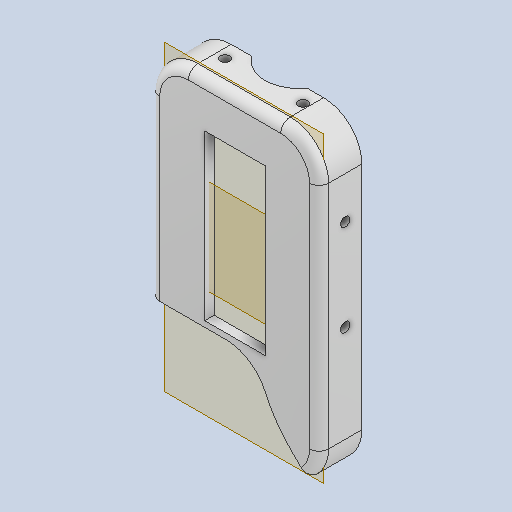
# Autodesk Inventor part: Pieza13
Saved by Autodesk Inventor 2025.2 (Build 292293000, 293)
## iProperties
Created: 2022-03-08
Part Number: Pieza13
Material: Aluminio
Document SubType Name: Modeling
Designer: Fabia
Density: 2.7 g/cm^3
Appearance: Satinado
Author: Fabia
Autodesk Inventor part; units mm, degrees
ref_plane "YZ Plane" through (0, 0, 0) normal (1, 0, 0) x (0, 1, 0)
ref_plane "XZ Plane" through (0, 0, 0) normal (0, 1, 0) x (-1, 0, 0)
ref_plane "Plano de trabajo1" through (0, 0, 1) normal (0, 0, 1) x (1, 0, 0)
sketch "Boceto1" plane through (0, 0, 1) normal (0, 0, 1) x (1, 0, 0)
  line L0 (-15.7261, -14.616) -> (-15.7261, 21.3302)
  arc A0 (-9.7062, 27.3501) -> (-15.7261, 21.3302) centre (-9.7062, 21.3302) ccw
  line L1 (-9.7062, 27.3501) -> (9.7062, 27.3501)
  arc A1 (15.7261, 21.3302) -> (9.7062, 27.3501) centre (9.7062, 21.3302) ccw
  line L2 (15.7261, 21.3302) -> (15.7261, -27.0568)
  arc A2 (13.9629, -31.3135) -> (15.7261, -27.0568) centre (9.7062, -27.0568) ccw
  line L3 (-17.7587, -14.616) -> (-17.7587, 21.3302)
  arc A3 (-9.7062, 29.3827) -> (-17.7587, 21.3302) centre (-9.7062, 21.3302) ccw
  line L4 (-9.7062, 29.3827) -> (9.7062, 29.3827)
  arc A4 (17.7587, 21.3302) -> (9.7062, 29.3827) centre (9.7062, 21.3302) ccw
  line L5 (17.7587, 21.3302) -> (17.7587, -27.0568)
  arc A5 (15.4002, -32.7508) -> (17.7587, -27.0568) centre (9.7062, -27.0568) ccw
  line L6 (15.4002, -32.7508) -> (13.9629, -31.3135)
  line L7 (15.4002, -32.7508) -> (7.7523, -32.7508)
  line L8 (7.7523, -32.7508) -> (7.7523, -15.933)
  line L9 (7.7523, -15.933) -> (-17.7587, -15.933)
  line L10 (-17.7587, -15.933) -> (-17.7587, -14.616)
  line L11 (-15.7261, -14.616) -> (-15.7261, -15.933)
  point P0 (0, 0)
  constraints: 24 end point, 12 point on circle, 6 centre point, 4 perpendicular, 1 horizontal, 1 point on line, 5 other
extrude "Extrusión1" add sketch "Boceto1" against normal blind 8 contours L11 L9 L10 L3 A3 L4 A4 L5 A5 L6 A2 L2 A1 L1 A0 L0
ref_plane "Plano de trabajo2" through (0, 0, 0) normal (0, 0, 1) x (1, 0, 0)
sketch "Boceto2" plane through (0, 0, 0) normal (0, 0, 1) x (1, 0, 0)
  arc A0 (-9.7062, 27.3501) -> (-15.7261, 21.3302) centre (-9.7062, 21.3302) ccw projected
  line L0 (-9.7062, 27.3501) -> (9.7062, 27.3501) projected
  arc A1 (15.7261, 21.3302) -> (9.7062, 27.3501) centre (9.7062, 21.3302) ccw projected
  line L1 (15.7261, 21.3302) -> (15.7261, -27.0568) projected
  arc A2 (13.9629, -31.3135) -> (15.7261, -27.0568) centre (9.7062, -27.0568) ccw projected
  line L2 (13.9629, -31.3135) -> (15.4002, -32.7508) projected
  arc A3 (15.4002, -32.7508) -> (17.7587, -27.0568) centre (9.7062, -27.0568) ccw projected
  line L3 (17.7587, -27.0568) -> (17.7587, 21.3302) projected
  arc A4 (17.7587, 21.3302) -> (9.7062, 29.3827) centre (9.7062, 21.3302) ccw projected
  line L4 (9.7062, 29.3827) -> (-9.7062, 29.3827) projected
  arc A5 (-9.7062, 29.3827) -> (-17.7587, 21.3302) centre (-9.7062, 21.3302) ccw projected
  line L5 (-17.7587, 21.3302) -> (-17.7587, -15.933) projected
  line L6 (-17.7587, -15.933) -> (-15.7261, -15.933) projected
  line L7 (-15.7261, -15.933) -> (-15.7261, 21.3302) projected
  line L8 (-18.3012, -15.933) -> (7.1636, -15.933)
  line L9 (7.1636, -15.933) -> (7.1636, -24.5142)
  line L10 (13.9629, -31.3135) -> (15.4002, -32.7508) projected
  line L11 (7.1636, -24.5142) -> (15.4002, -32.7508)
  line L12 (6.5068, 19.8394) -> (-6.2947, 19.8394)
  line L13 (-6.2947, 19.8394) -> (-6.2947, -14.7203)
  line L14 (-6.2947, -14.7203) -> (6.5068, -14.7203)
  line L15 (6.5068, -14.7203) -> (6.5068, 19.8394)
  point P0 (0, 0)
  constraints: 14 end point, 2 horizontal, 2 parallel, 2 perpendicular
extrude "Extrusión2" add sketch "Boceto2" along normal blind 2
fillet "Empalme1" radius 2 6 edges at (15.4002, 27.0242, 2) (0, 29.3827, 2) (-15.4002, 27.0242, 2) (-17.7587, 2.6986, 2) (17.1458, -30.1384, 2) (17.7587, -2.8633, 2)
fillet "Empalme2" radius 9 1 edges at (7.1636, -15.933, 1)
fillet "Empalme3" radius 26.75 1 edges at (7.1636, -24.5142, 1)
sketch "Boceto3" plane through (-17.7587, -15.933, -7) normal (-1, 0, 0) x (0, 0, 1)
  line L0 (7, 37.2632) -> (0, 37.2632) projected
  line L1 (0, 0) -> (7, 0) projected
  circle A0 centre (3.5, 28.4783) radius 0.9798
  circle A1 centre (3.5, 9.3158) radius 1
  point P0 (7, 15.933)
  dimension "d10" = 2
  constraints: 2 centre point
  measures "d10" diameter of A1
extrude "Extrusión3" cut sketch "Boceto3" against normal blind 122
sketch "Boceto5" plane through (-9.7062, 29.3827, -7) normal (0, 1, 0) x (1, 0, 0)
  arc A0 (3.6376, 1.2526) -> (16.4545, 0.9506) centre (10.1143, 4) ccw
  line L0 (16.4545, 0.9506) -> (3.6376, 1.2526)
  point P0 (9.7062, -7)
  constraints: 2 end point, 2 point on circle, 1 centre point
extrude "Extrusión5" cut sketch "Boceto5" against normal blind 7
sketch "Boceto4" plane through (-9.7062, 29.3827, -7) normal (0, 1, 0) x (1, 0, 0)
  circle A0 centre (1.9654, -3.2358) radius 1
  circle A1 centre (18.267, -3.2358) radius 1
  point P0 (9.7062, -7)
  dimension "d11" = 2
  dimension "d16" = 2
  constraints: 2 centre point
  measures "d11" diameter of A0
  measures "d16" diameter of A1
extrude "Extrusión4" cut sketch "Boceto4" against normal blind 3
